Autodesk Fusion 360 part; units mm, degrees
(part 3 of 5)
sketch "gear (2)" plane through (0, 39.4, 0) normal (0, 1, 0) x (1, 0, 0) in component "Gripper gear L (printed)"
  line L0 (-136.5803, 1.2704) -> (-136.628, 0.595)
  line L1 (-136.628, 0.595) -> (-136.6893, 0.3367)
  line L2 (-136.6893, 0.3367) -> (-136.7881, 0.0815)
  line L3 (-136.7881, 0.0815) -> (-136.913, -0.1705)
  line L4 (-136.913, -0.1705) -> (-137.0604, -0.4192)
  line L5 (-137.0604, -0.4192) -> (-137.2282, -0.6639)
  line L6 (-137.2282, -0.6639) -> (-137.4152, -0.9042)
  line L7 (-137.4152, -0.9042) -> (-138.0397, -0.8)
  line L8 (-138.0397, -0.8) -> (-138.1385, -0.512)
  line L9 (-138.1385, -0.512) -> (-138.2178, -0.226)
  line L10 (-138.2178, -0.226) -> (-138.2765, 0.057)
  line L11 (-138.2765, 0.057) -> (-138.3128, 0.336)
  line L12 (-138.3128, 0.336) -> (-138.3234, 0.6093)
  line L13 (-138.3234, 0.6093) -> (-138.2975, 0.8736)
  line L14 (-138.2975, 0.8736) -> (-138.1233, 1.5279)
  line L15 (-138.1233, 1.5279) -> (-138.4949, 1.6363)
  line L16 (-138.4949, 1.6363) -> (-138.8611, 1.762)
  line L17 (-138.8611, 1.762) -> (-139.221, 1.9048)
  line L18 (-139.221, 1.9048) -> (-139.4854, 1.2814)
  line L19 (-139.4854, 1.2814) -> (-139.6273, 1.057)
  line L20 (-139.6273, 1.057) -> (-139.8036, 0.8477)
  line L21 (-139.8036, 0.8477) -> (-140.0036, 0.6499)
  line L22 (-140.0036, 0.6499) -> (-140.2237, 0.4626)
  line L23 (-140.2237, 0.4626) -> (-140.4619, 0.2856)
  line L24 (-140.4619, 0.2856) -> (-140.7167, 0.119)
  line L25 (-140.7167, 0.119) -> (-141.2736, 0.4204)
  line L26 (-141.2736, 0.4204) -> (-141.2736, 0.7249)
  line L27 (-141.2736, 0.7249) -> (-141.2557, 1.0211)
  line L28 (-141.2557, 1.0211) -> (-141.2193, 1.3078)
  line L29 (-141.2193, 1.3078) -> (-141.163, 1.5835)
  line L30 (-141.163, 1.5835) -> (-141.0843, 1.8454)
  line L31 (-141.0843, 1.8454) -> (-140.974, 2.087)
  line L32 (-140.974, 2.087) -> (-140.5967, 2.6493)
  line L33 (-140.5967, 2.6493) -> (-140.9131, 2.8725)
  line L34 (-140.9131, 2.8725) -> (-141.2186, 3.1103)
  line L35 (-141.2186, 3.1103) -> (-141.5127, 3.3622)
  line L36 (-141.5127, 3.3622) -> (-141.9651, 2.8584)
  line L37 (-141.9651, 2.8584) -> (-142.1722, 2.6922)
  line L38 (-142.1722, 2.6922) -> (-142.4069, 2.5515)
  line L39 (-142.4069, 2.5515) -> (-142.6603, 2.4294)
  line L40 (-142.6603, 2.4294) -> (-142.9293, 2.3237)
  line L41 (-142.9293, 2.3237) -> (-143.212, 2.2336)
  line L42 (-143.212, 2.2336) -> (-143.5072, 2.1588)
  line L43 (-143.5072, 2.1588) -> (-143.936, 2.6247)
  line L44 (-143.936, 2.6247) -> (-143.8371, 2.9126)
  line L45 (-143.8371, 2.9126) -> (-143.724, 3.187)
  line L46 (-143.724, 3.187) -> (-143.5965, 3.4464)
  line L47 (-143.5965, 3.4464) -> (-143.4538, 3.6888)
  line L48 (-143.4538, 3.6888) -> (-143.2942, 3.9111)
  line L49 (-143.2942, 3.9111) -> (-143.1115, 4.1037)
  line L50 (-143.1115, 4.1037) -> (-142.5721, 4.513)
  line L51 (-142.5721, 4.513) -> (-142.7988, 4.8269)
  line L52 (-142.7988, 4.8269) -> (-143.0106, 5.151)
  line L53 (-143.0106, 5.151) -> (-143.2069, 5.4847)
  line L54 (-143.2069, 5.4847) -> (-143.7984, 5.1551)
  line L55 (-143.7984, 5.1551) -> (-144.0483, 5.0652)
  line L56 (-144.0483, 5.0652) -> (-144.3159, 5.0083)
  line L57 (-144.3159, 5.0083) -> (-144.5952, 4.9751)
  line L58 (-144.5952, 4.9751) -> (-144.884, 4.9624)
  line L59 (-144.884, 4.9624) -> (-145.1807, 4.9691)
  line L60 (-145.1807, 4.9691) -> (-145.4841, 4.9942)
  line L61 (-145.4841, 4.9942) -> (-145.7384, 5.5741)
  line L62 (-145.7384, 5.5741) -> (-145.5514, 5.8143)
  line L63 (-145.5514, 5.8143) -> (-145.3553, 6.037)
  line L64 (-145.3553, 6.037) -> (-145.1505, 6.241)
  line L65 (-145.1505, 6.241) -> (-144.9368, 6.4239)
  line L66 (-144.9368, 6.4239) -> (-144.7137, 6.5823)
  line L67 (-144.7137, 6.5823) -> (-144.4783, 6.7052)
  line L68 (-144.4783, 6.7052) -> (-143.8353, 6.9172)
  line L69 (-143.8353, 6.9172) -> (-143.9478, 7.2876)
  line L70 (-143.9478, 7.2876) -> (-144.0429, 7.663)
  line L71 (-144.0429, 7.663) -> (-144.1202, 8.0423)
  line L72 (-144.1202, 8.0423) -> (-144.7866, 7.9227)
  line L73 (-144.7866, 7.9227) -> (-145.0522, 7.9188)
  line L74 (-145.0522, 7.9188) -> (-145.3237, 7.9519)
  line L75 (-145.3237, 7.9519) -> (-145.5988, 8.0111)
  line L76 (-145.5988, 8.0111) -> (-145.876, 8.0929)
  line L77 (-145.876, 8.0929) -> (-146.1544, 8.1955)
  line L78 (-146.1544, 8.1955) -> (-146.4332, 8.3178)
  line L79 (-146.4332, 8.3178) -> (-146.4855, 8.9488)
  line L80 (-146.4855, 8.9488) -> (-146.2306, 9.1153)
  line L81 (-146.2306, 9.1153) -> (-145.9729, 9.2624)
  line L82 (-145.9729, 9.2624) -> (-145.7129, 9.3887)
  line L83 (-145.7129, 9.3887) -> (-145.4514, 9.4924)
  line L84 (-145.4514, 9.4924) -> (-145.189, 9.5697)
  line L85 (-145.189, 9.5697) -> (-144.9264, 9.6096)
  line L86 (-144.9264, 9.6096) -> (-144.2494, 9.6012)
  line L87 (-144.2494, 9.6012) -> (-144.2355, 9.9882)
  line L88 (-144.2355, 9.9882) -> (-144.2036, 10.374)
  line L89 (-144.2036, 10.374) -> (-144.1535, 10.7579)
  line L90 (-144.1535, 10.7579) -> (-144.8227, 10.8612)
  line L91 (-144.8227, 10.8612) -> (-145.0751, 10.9437)
  line L92 (-145.0751, 10.9437) -> (-145.3212, 11.0632)
  line L93 (-145.3212, 11.0632) -> (-145.5621, 11.2085)
  line L94 (-145.5621, 11.2085) -> (-145.7977, 11.3759)
  line L95 (-145.7977, 11.3759) -> (-146.0278, 11.5634)
  line L96 (-146.0278, 11.5634) -> (-146.2518, 11.7695)
  line L97 (-146.2518, 11.7695) -> (-146.0964, 12.3833)
  line L98 (-146.0964, 12.3833) -> (-145.8012, 12.458)
  line L99 (-145.8012, 12.458) -> (-145.5097, 12.5134)
  line L100 (-145.5097, 12.5134) -> (-145.2228, 12.5485)
  line L101 (-145.2228, 12.5485) -> (-144.9418, 12.5617)
  line L102 (-144.9418, 12.5617) -> (-144.6684, 12.5496)
  line L103 (-144.6684, 12.5496) -> (-144.4072, 12.502)
  line L104 (-144.4072, 12.502) -> (-143.7695, 12.2743)
  line L105 (-143.7695, 12.2743) -> (-143.6308, 12.6358)
  line L106 (-143.6308, 12.6358) -> (-143.4753, 12.9904)
  line L107 (-143.4753, 12.9904) -> (-143.3033, 13.3372)
  line L108 (-143.3033, 13.3372) -> (-143.9027, 13.6521)
  line L109 (-143.9027, 13.6521) -> (-144.1147, 13.8121)
  line L110 (-144.1147, 13.8121) -> (-144.3086, 14.0051)
  line L111 (-144.3086, 14.0051) -> (-144.4893, 14.2207)
  line L112 (-144.4893, 14.2207) -> (-144.6578, 14.4556)
  line L113 (-144.6578, 14.4556) -> (-144.8145, 14.7076)
  line L114 (-144.8145, 14.7076) -> (-144.9594, 14.9753)
  line L115 (-144.9594, 14.9753) -> (-144.6131, 15.5054)
  line L116 (-144.6131, 15.5054) -> (-144.3097, 15.4802)
  line L117 (-144.3097, 15.4802) -> (-144.016, 15.4379)
  line L118 (-144.016, 15.4379) -> (-143.7332, 15.378)
  line L119 (-143.7332, 15.378) -> (-143.4631, 15.2992)
  line L120 (-143.4631, 15.2992) -> (-143.2086, 15.199)
  line L121 (-143.2086, 15.199) -> (-142.9769, 15.0692)
  line L122 (-142.9769, 15.0692) -> (-142.4477, 14.6468)
  line L123 (-142.4477, 14.6468) -> (-142.1992, 14.9436)
  line L124 (-142.1992, 14.9436) -> (-141.9369, 15.2285)
  line L125 (-141.9369, 15.2285) -> (-141.6616, 15.5007)
  line L126 (-141.6616, 15.5007) -> (-142.1263, 15.9932)
  line L127 (-142.1263, 15.9932) -> (-142.2748, 16.2133)
  line L128 (-142.2748, 16.2133) -> (-142.3956, 16.4588)
  line L129 (-142.3956, 16.4588) -> (-142.4965, 16.7214)
  line L130 (-142.4965, 16.7214) -> (-142.5796, 16.9982)
  line L131 (-142.5796, 16.9982) -> (-142.646, 17.2875)
  line L132 (-142.646, 17.2875) -> (-142.6961, 17.5877)
  line L133 (-142.6961, 17.5877) -> (-142.1965, 17.9767)
  line L134 (-142.1965, 17.9767) -> (-141.9177, 17.8543)
  line L135 (-141.9177, 17.8543) -> (-141.6536, 17.719)
  line L136 (-141.6536, 17.719) -> (-141.4056, 17.5704)
  line L137 (-141.4056, 17.5704) -> (-141.1758, 17.4082)
  line L138 (-141.1758, 17.4082) -> (-140.9675, 17.2308)
  line L139 (-140.9675, 17.2308) -> (-140.7906, 17.0328)
  line L140 (-140.7906, 17.0328) -> (-140.4272, 16.4615)
  line L141 (-140.4272, 16.4615) -> (-140.0957, 16.6615)
  line L142 (-140.0957, 16.6615) -> (-139.7552, 16.8458)
  line L143 (-139.7552, 16.8458) -> (-139.4065, 17.0139)
  line L144 (-139.4065, 17.0139) -> (-139.686, 17.6306)
  line L145 (-139.686, 17.6306) -> (-139.755, 17.887)
  line L146 (-139.755, 17.887) -> (-139.7896, 18.1584)
  line L147 (-139.7896, 18.1584) -> (-139.7997, 18.4395)
  line L148 (-139.7997, 18.4395) -> (-139.7884, 18.7283)
  line L149 (-139.7884, 18.7283) -> (-139.7573, 19.0235)
  line L150 (-139.7573, 19.0235) -> (-139.7072, 19.3238)
  line L151 (-139.7072, 19.3238) -> (-139.1083, 19.5294)
  line L152 (-139.1083, 19.5294) -> (-138.8844, 19.3231)
  line L153 (-138.8844, 19.3231) -> (-138.6786, 19.1094)
  line L154 (-138.6786, 19.1094) -> (-138.4923, 18.8884)
  line L155 (-138.4923, 18.8884) -> (-138.3276, 18.6603)
  line L156 (-138.3276, 18.6603) -> (-138.1881, 18.4249)
  line L157 (-138.1881, 18.4249) -> (-138.0851, 18.1802)
  line L158 (-138.0851, 18.1802) -> (-137.927, 17.5218)
  line L159 (-137.927, 17.5218) -> (-137.5485, 17.6034)
  line L160 (-137.5485, 17.6034) -> (-137.1666, 17.6671)
  line L161 (-137.1666, 17.6671) -> (-136.7821, 17.7128)
  line L162 (-136.7821, 17.7128) -> (-136.8463, 18.3869)
  line L163 (-136.8463, 18.3869) -> (-136.8283, 18.6518)
  line L164 (-136.8283, 18.6518) -> (-136.7729, 18.9197)
  line L165 (-136.7729, 18.9197) -> (-136.6912, 19.1889)
  line L166 (-136.6912, 19.1889) -> (-136.5867, 19.4584)
  line L167 (-136.5867, 19.4584) -> (-136.4615, 19.7274)
  line L168 (-136.4615, 19.7274) -> (-136.3166, 19.9952)
  line L169 (-136.3166, 19.9952) -> (-135.6834, 19.9952)
  line L170 (-135.6834, 19.9952) -> (-135.5385, 19.7274)
  line L171 (-135.5385, 19.7274) -> (-135.4133, 19.4584)
  line L172 (-135.4133, 19.4584) -> (-135.3088, 19.1889)
  line L173 (-135.3088, 19.1889) -> (-135.2271, 18.9197)
  line L174 (-135.2271, 18.9197) -> (-135.1717, 18.6518)
  line L175 (-135.1717, 18.6518) -> (-135.1537, 18.3869)
  line L176 (-135.1537, 18.3869) -> (-135.2179, 17.7128)
  line L177 (-135.2179, 17.7128) -> (-134.8334, 17.6671)
  line L178 (-134.8334, 17.6671) -> (-134.4515, 17.6034)
  line L179 (-134.4515, 17.6034) -> (-134.073, 17.5218)
  line L180 (-134.073, 17.5218) -> (-133.9149, 18.1802)
  line L181 (-133.9149, 18.1802) -> (-133.8119, 18.4249)
  line L182 (-133.8119, 18.4249) -> (-133.6724, 18.6603)
  line L183 (-133.6724, 18.6603) -> (-133.5077, 18.8884)
  line L184 (-133.5077, 18.8884) -> (-133.3214, 19.1094)
  line L185 (-133.3214, 19.1094) -> (-133.1156, 19.3231)
  line L186 (-133.1156, 19.3231) -> (-132.8917, 19.5294)
  line L187 (-132.8917, 19.5294) -> (-132.2928, 19.3238)
  line L188 (-132.2928, 19.3238) -> (-132.2427, 19.0235)
  line L189 (-132.2427, 19.0235) -> (-132.2116, 18.7283)
  line L190 (-132.2116, 18.7283) -> (-132.2003, 18.4395)
  line L191 (-132.2003, 18.4395) -> (-132.2104, 18.1584)
  line L192 (-132.2104, 18.1584) -> (-132.245, 17.887)
  line L193 (-132.245, 17.887) -> (-132.314, 17.6306)
  line L194 (-132.314, 17.6306) -> (-132.5935, 17.0139)
  line L195 (-132.5935, 17.0139) -> (-132.2448, 16.8458)
  line L196 (-132.2448, 16.8458) -> (-131.9043, 16.6615)
  line L197 (-131.9043, 16.6615) -> (-131.5728, 16.4615)
  line L198 (-131.5728, 16.4615) -> (-131.2094, 17.0328)
  line L199 (-131.2094, 17.0328) -> (-131.0325, 17.2308)
  line L200 (-131.0325, 17.2308) -> (-130.8242, 17.4082)
  line L201 (-130.8242, 17.4082) -> (-130.5944, 17.5704)
  line L202 (-130.5944, 17.5704) -> (-130.3464, 17.719)
  line L203 (-130.3464, 17.719) -> (-130.0823, 17.8543)
  line L204 (-130.0823, 17.8543) -> (-129.8035, 17.9767)
  line L205 (-129.8035, 17.9767) -> (-129.3039, 17.5877)
  line L206 (-129.3039, 17.5877) -> (-129.354, 17.2875)
  line L207 (-129.354, 17.2875) -> (-129.4204, 16.9982)
  line L208 (-129.4204, 16.9982) -> (-129.5035, 16.7214)
  line L209 (-129.5035, 16.7214) -> (-129.6044, 16.4588)
  line L210 (-129.6044, 16.4588) -> (-129.7252, 16.2133)
  line L211 (-129.7252, 16.2133) -> (-129.8737, 15.9932)
  line L212 (-129.8737, 15.9932) -> (-130.3384, 15.5007)
  line L213 (-130.3384, 15.5007) -> (-130.0631, 15.2285)
  line L214 (-130.0631, 15.2285) -> (-129.8008, 14.9436)
  line L215 (-129.8008, 14.9436) -> (-129.5523, 14.6468)
  line L216 (-129.5523, 14.6468) -> (-129.0231, 15.0692)
  line L217 (-129.0231, 15.0692) -> (-128.7914, 15.199)
  line L218 (-128.7914, 15.199) -> (-128.5369, 15.2992)
  line L219 (-128.5369, 15.2992) -> (-128.2668, 15.378)
  line L220 (-128.2668, 15.378) -> (-127.984, 15.4379)
  line L221 (-127.984, 15.4379) -> (-127.6903, 15.4802)
  line L222 (-127.6903, 15.4802) -> (-127.3869, 15.5054)
  line L223 (-127.3869, 15.5054) -> (-127.0406, 14.9753)
  line L224 (-127.0406, 14.9753) -> (-127.1855, 14.7076)
  line L225 (-127.1855, 14.7076) -> (-127.3422, 14.4556)
  line L226 (-127.3422, 14.4556) -> (-127.5107, 14.2207)
  line L227 (-127.5107, 14.2207) -> (-127.6914, 14.0051)
  line L228 (-127.6914, 14.0051) -> (-127.8853, 13.8121)
  line L229 (-127.8853, 13.8121) -> (-128.0973, 13.6521)
  line L230 (-128.0973, 13.6521) -> (-128.6967, 13.3372)
  line L231 (-128.6967, 13.3372) -> (-128.5247, 12.9904)
  line L232 (-128.5247, 12.9904) -> (-128.3692, 12.6358)
  line L233 (-128.3692, 12.6358) -> (-128.2305, 12.2743)
  line L234 (-128.2305, 12.2743) -> (-127.5928, 12.502)
  line L235 (-127.5928, 12.502) -> (-127.3316, 12.5496)
  line L236 (-127.3316, 12.5496) -> (-127.0582, 12.5617)
  line L237 (-127.0582, 12.5617) -> (-126.7772, 12.5485)
  line L238 (-126.7772, 12.5485) -> (-126.4903, 12.5134)
  line L239 (-126.4903, 12.5134) -> (-126.1988, 12.458)
  line L240 (-126.1988, 12.458) -> (-125.9036, 12.3833)
  line L241 (-125.9036, 12.3833) -> (-125.7482, 11.7695)
  line L242 (-125.7482, 11.7695) -> (-125.9722, 11.5634)
  line L243 (-125.9722, 11.5634) -> (-126.2023, 11.3759)
  line L244 (-126.2023, 11.3759) -> (-126.4379, 11.2085)
  line L245 (-126.4379, 11.2085) -> (-126.6788, 11.0632)
  line L246 (-126.6788, 11.0632) -> (-126.9249, 10.9437)
  line L247 (-126.9249, 10.9437) -> (-127.1773, 10.8612)
  line L248 (-127.1773, 10.8612) -> (-127.8465, 10.7579)
  line L249 (-127.8465, 10.7579) -> (-127.7964, 10.374)
  line L250 (-127.7964, 10.374) -> (-127.7645, 9.9882)
  line L251 (-127.7645, 9.9882) -> (-127.7506, 9.6012)
  line L252 (-127.7506, 9.6012) -> (-127.0736, 9.6096)
  line L253 (-127.0736, 9.6096) -> (-126.811, 9.5697)
  line L254 (-126.811, 9.5697) -> (-126.5486, 9.4924)
  line L255 (-126.5486, 9.4924) -> (-126.2871, 9.3887)
  line L256 (-126.2871, 9.3887) -> (-126.0271, 9.2624)
  line L257 (-126.0271, 9.2624) -> (-125.7694, 9.1153)
  line L258 (-125.7694, 9.1153) -> (-125.5145, 8.9488)
  line L259 (-125.5145, 8.9488) -> (-125.5668, 8.3178)
  line L260 (-125.5668, 8.3178) -> (-125.8456, 8.1955)
  line L261 (-125.8456, 8.1955) -> (-126.124, 8.0929)
  line L262 (-126.124, 8.0929) -> (-126.4012, 8.0111)
  line L263 (-126.4012, 8.0111) -> (-126.6763, 7.9519)
  line L264 (-126.6763, 7.9519) -> (-126.9478, 7.9188)
  line L265 (-126.9478, 7.9188) -> (-127.2134, 7.9227)
  line L266 (-127.2134, 7.9227) -> (-127.8798, 8.0423)
  line L267 (-127.8798, 8.0423) -> (-127.9571, 7.663)
  line L268 (-127.9571, 7.663) -> (-128.0522, 7.2876)
  line L269 (-128.0522, 7.2876) -> (-128.1647, 6.9172)
  line L270 (-128.1647, 6.9172) -> (-127.5217, 6.7052)
  line L271 (-127.5217, 6.7052) -> (-127.2863, 6.5823)
  line L272 (-127.2863, 6.5823) -> (-127.0632, 6.4239)
  line L273 (-127.0632, 6.4239) -> (-126.8495, 6.241)
  line L274 (-126.8495, 6.241) -> (-126.6447, 6.037)
  line L275 (-126.6447, 6.037) -> (-126.4486, 5.8143)
  line L276 (-126.4486, 5.8143) -> (-126.2616, 5.5741)
  line L277 (-126.2616, 5.5741) -> (-126.5159, 4.9942)
  line L278 (-126.5159, 4.9942) -> (-126.8193, 4.9691)
  line L279 (-126.8193, 4.9691) -> (-127.116, 4.9624)
  line L280 (-127.116, 4.9624) -> (-127.4048, 4.9751)
  line L281 (-127.4048, 4.9751) -> (-127.6841, 5.0083)
  line L282 (-127.6841, 5.0083) -> (-127.9517, 5.0652)
  line L283 (-127.9517, 5.0652) -> (-128.2016, 5.1551)
  line L284 (-128.2016, 5.1551) -> (-128.7931, 5.4847)
  line L285 (-128.7931, 5.4847) -> (-128.9894, 5.151)
  line L286 (-128.9894, 5.151) -> (-129.2012, 4.8269)
  line L287 (-129.2012, 4.8269) -> (-129.4279, 4.513)
  line L288 (-129.4279, 4.513) -> (-128.8885, 4.1037)
  line L289 (-128.8885, 4.1037) -> (-128.7058, 3.9111)
  line L290 (-128.7058, 3.9111) -> (-128.5462, 3.6888)
  line L291 (-128.5462, 3.6888) -> (-128.4035, 3.4464)
  line L292 (-128.4035, 3.4464) -> (-128.276, 3.187)
  line L293 (-128.276, 3.187) -> (-128.1629, 2.9126)
  line L294 (-128.1629, 2.9126) -> (-128.064, 2.6247)
  line L295 (-128.064, 2.6247) -> (-128.4928, 2.1588)
  line L296 (-128.4928, 2.1588) -> (-128.788, 2.2336)
  line L297 (-128.788, 2.2336) -> (-129.0707, 2.3237)
  line L298 (-129.0707, 2.3237) -> (-129.3397, 2.4294)
  line L299 (-129.3397, 2.4294) -> (-129.5931, 2.5515)
  line L300 (-129.5931, 2.5515) -> (-129.8278, 2.6922)
  line L301 (-129.8278, 2.6922) -> (-130.0349, 2.8584)
  line L302 (-130.0349, 2.8584) -> (-130.4873, 3.3622)
  line L303 (-130.4873, 3.3622) -> (-130.7814, 3.1103)
  line L304 (-130.7814, 3.1103) -> (-131.0869, 2.8725)
  line L305 (-131.0869, 2.8725) -> (-131.4033, 2.6493)
  line L306 (-131.4033, 2.6493) -> (-131.026, 2.087)
  line L307 (-131.026, 2.087) -> (-130.9157, 1.8454)
  line L308 (-130.9157, 1.8454) -> (-130.837, 1.5835)
  line L309 (-130.837, 1.5835) -> (-130.7807, 1.3078)
  line L310 (-130.7807, 1.3078) -> (-130.7443, 1.0211)
  line L311 (-130.7443, 1.0211) -> (-130.7264, 0.7249)
  line L312 (-130.7264, 0.7249) -> (-130.7264, 0.4204)
  line L313 (-130.7264, 0.4204) -> (-131.2833, 0.119)
  line L314 (-131.2833, 0.119) -> (-131.5381, 0.2856)
  line L315 (-131.5381, 0.2856) -> (-131.7763, 0.4626)
  line L316 (-131.7763, 0.4626) -> (-131.9964, 0.6499)
  line L317 (-131.9964, 0.6499) -> (-132.1964, 0.8477)
  line L318 (-132.1964, 0.8477) -> (-132.3727, 1.057)
  line L319 (-132.3727, 1.057) -> (-132.5146, 1.2814)
  line L320 (-132.5146, 1.2814) -> (-132.779, 1.9048)
  line L321 (-132.779, 1.9048) -> (-133.1389, 1.762)
  line L322 (-133.1389, 1.762) -> (-133.5051, 1.6363)
  line L323 (-133.5051, 1.6363) -> (-133.8767, 1.5279)
  line L324 (-133.8767, 1.5279) -> (-133.7025, 0.8736)
  line L325 (-133.7025, 0.8736) -> (-133.6766, 0.6093)
  line L326 (-133.6766, 0.6093) -> (-133.6872, 0.336)
  line L327 (-133.6872, 0.336) -> (-133.7235, 0.057)
  line L328 (-133.7235, 0.057) -> (-133.7822, -0.226)
  line L329 (-133.7822, -0.226) -> (-133.8615, -0.512)
  line L330 (-133.8615, -0.512) -> (-133.9603, -0.8)
  line L331 (-133.9603, -0.8) -> (-134.5848, -0.9042)
  line L332 (-134.5848, -0.9042) -> (-134.7718, -0.6639)
  line L333 (-134.7718, -0.6639) -> (-134.9396, -0.4192)
  line L334 (-134.9396, -0.4192) -> (-135.087, -0.1705)
  line L335 (-135.087, -0.1705) -> (-135.2119, 0.0815)
  line L336 (-135.2119, 0.0815) -> (-135.3107, 0.3367)
  line L337 (-135.3107, 0.3367) -> (-135.372, 0.595)
  line L338 (-135.372, 0.595) -> (-135.4197, 1.2704)
  line L339 (-135.4197, 1.2704) -> (-135.8064, 1.2523)
  line L340 (-135.8064, 1.2523) -> (-136.1936, 1.2523)
  line L341 (-136.1936, 1.2523) -> (-136.5803, 1.2704)
extrude "gear (1)'" add sketch "gear (2)" along normal blind 6 separate body makes body 23 in component "Gripper gear L (printed)"
sketch "finger tongue (2)" plane through (0, 39.4, 0) normal (0, 1, 0) x (1, 0, 0) in component "Gripper gear L (printed)"
  line L0 (-131, 13.5) -> (-108, 13.5)
  line L1 (-108, 13.5) -> (-108, 5.5)
  line L2 (-108, 5.5) -> (-131, 5.5)
  line L3 (-131, 5.5) -> (-131, 13.5)
extrude "finger tongue (1)'" add sketch "finger tongue (2)" along normal blind 6 separate body makes body 24 in component "Gripper gear L (printed)"
combine "Combine1'''" operation add target body 23 tool bodies 24 in component "Gripper gear L (printed)"
ref_plane "WorkPlane2" through (0, 38.4, 0) normal (0, 1, 0) x (0, 0, 1) in component "Gripper gear L (printed)"
sketch "axle bore (2)" plane through (0, 38.4, 0) normal (0, 1, 0) x (1, 0, 0) in component "Gripper gear L (printed)"
  circle A0 centre (-136, 9.5) radius 1.7
extrude "axle bore (1)'" cut sketch "axle bore (2)" along normal blind 8 bodies 23 in component "Gripper gear L (printed)"
sketch "finger insert hole (2)" plane through (0, 38.4, 0) normal (0, 1, 0) x (1, 0, 0) in component "Gripper gear L (printed)"
  circle A0 centre (-114, 9.5) radius 2
extrude "finger insert hole (1)'" cut sketch "finger insert hole (2)" along normal blind 8 bodies 23 in component "Gripper gear L (printed)"
ref_plane "WorkPlane1" through (0, 0, -4) normal (0, 0, 1) x (1, 0, 0) in component "Gripper trigger (printed)"
sketch "lever" plane through (0, 0, -4) normal (0, 0, 1) x (1, 0, 0) in component "Gripper trigger (printed)"
  line L0 (103.845, -2.8975) -> (106.6597, -9.2424)
  line L1 (106.6597, -9.2424) -> (109.3343, -15.6275)
  line L2 (109.3343, -15.6275) -> (111.7503, -22.0868)
  line L3 (111.7503, -22.0868) -> (113.8282, -28.6431)
  line L4 (113.8282, -28.6431) -> (115.5403, -35.3042)
  line L5 (115.5403, -35.3042) -> (116.9144, -42.0622)
  line L6 (116.9144, -42.0622) -> (118.0297, -48.8945)
  line L7 (118.0297, -48.8945) -> (119.0051, -55.7668)
  line L8 (119.0051, -55.7668) -> (111.315, -57.9719)
  line L9 (111.315, -57.9719) -> (96.155, -5.1025)
  line L10 (96.155, -5.1025) -> (103.845, -2.8975)
extrude "lever (1)" add sketch "lever" along normal blind 20 separate body makes body 25 in component "Gripper trigger (printed)"
ref_plane "WorkPlane2" through (0, 0, -3.99) normal (0, 0, 1) x (1, 0, 0) in component "Gripper trigger (printed)"
sketch "eye" plane through (0, 0, -3.99) normal (0, 0, 1) x (1, 0, 0) in component "Gripper trigger (printed)"
  circle A0 centre (100, -4) radius 5
extrude "eye (1)" add sketch "eye" along normal blind 23.98 separate body makes body 26 in component "Gripper trigger (printed)"
ref_plane "WorkPlane3" through (0, 0, 12) normal (0, 0, 1) x (1, 0, 0) in component "Gripper trigger (printed)"
sketch "cable horn" plane through (0, 0, 12) normal (0, 0, 1) x (1, 0, 0) in component "Gripper trigger (printed)"
  line L0 (95, -4) -> (105, -4)
  line L1 (105, -4) -> (105, 17)
  line L2 (105, 17) -> (95, 17)
  line L3 (95, 17) -> (95, -4)
extrude "cable horn (1)" add sketch "cable horn" along normal blind 8 separate body makes body 27 in component "Gripper trigger (printed)"
combine "Combine1''''" operation add target body 25 tool bodies 26 in component "Gripper trigger (printed)"
combine "Combine2'''" operation add target body 25 tool bodies 27 in component "Gripper trigger (printed)"
ref_plane "WorkPlane4" through (0, 0, -5) normal (0, 0, 1) x (1, 0, 0) in component "Gripper trigger (printed)"
sketch "pivot bore" plane through (0, 0, -5) normal (0, 0, 1) x (1, 0, 0) in component "Gripper trigger (printed)"
  circle A0 centre (100, -4) radius 1.7
extrude "pivot bore (1)" cut sketch "pivot bore" along normal blind 27 bodies 25 in component "Gripper trigger (printed)"
ref_plane "WorkPlane5" through (0, 0, 15.1) normal (0, 0, 1) x (1, 0, 0) in component "Gripper trigger (printed)"
sketch "wire slot" plane through (0, 0, 15.1) normal (0, 0, 1) x (1, 0, 0) in component "Gripper trigger (printed)"
  line L0 (94, 12.6) -> (106, 12.6)
  line L1 (106, 12.6) -> (106, 18)
  line L2 (106, 18) -> (94, 18)
  line L3 (94, 18) -> (94, 12.6)
extrude "wire slot (1)" cut sketch "wire slot" along normal blind 1.8 bodies 25 in component "Gripper trigger (printed)"
ref_plane "WorkPlane1" through (0, 24.2, 0) normal (0, 1, 0) x (0, 0, 1) in component "Gripper pusher (printed)"
sketch "lever (2)" plane through (0, 24.2, 0) normal (0, 1, 0) x (1, 0, 0) in component "Gripper pusher (printed)"
  line L0 (125.993, -57.7785) -> (124.693, -37.2785)
  line L1 (124.693, -37.2785) -> (117.707, -37.7215)
  line L2 (117.707, -37.7215) -> (119.007, -58.2215)
  line L3 (119.007, -58.2215) -> (125.993, -57.7785)
extrude "lever (1)'" add sketch "lever (2)" along normal blind 4.8 separate body makes body 28 in component "Gripper pusher (printed)"
sketch "hub" plane through (0, 24.2, 0) normal (0, 1, 0) x (1, 0, 0) in component "Gripper pusher (printed)"
  circle A0 centre (122.5, -58) radius 5
extrude "hub (1)" add sketch "hub" along normal blind 4.8 separate body makes body 29 in component "Gripper pusher (printed)"
combine "Combine1'''''" operation add target body 28 tool bodies 29 in component "Gripper pusher (printed)"
ref_plane "WorkPlane2" through (0, 23.2, 0) normal (0, 1, 0) x (0, 0, 1) in component "Gripper pusher (printed)"
sketch "pivot hole" plane through (0, 23.2, 0) normal (0, 1, 0) x (1, 0, 0) in component "Gripper pusher (printed)"
  circle A0 centre (122.5, -58) radius 1.7
extrude "pivot hole (1)" cut sketch "pivot hole" along normal blind 7 bodies 28 in component "Gripper pusher (printed)"
ref_plane "WorkPlane3" through (116.1203, 0, 0) normal (1, 0, 0) x (0, 1, 0) in component "Gripper pusher (printed)"
sketch "cable hole" plane through (116.1203, 0, 0) normal (1, 0, 0) x (0, 0, -1) in component "Gripper pusher (printed)"
  circle A0 centre (-52.012, 26.6) radius 0.9
extrude "cable hole (1)" cut sketch "cable hole" along normal blind 12 bodies 28 in component "Gripper pusher (printed)"
ref_plane "WorkPlane1" through (0, 0, -12) normal (0, 0, 1) x (1, 0, 0) in component "Gripper handle (printed)"
sketch "arm" plane through (0, 0, -12) normal (0, 0, 1) x (1, 0, 0) in component "Gripper handle (printed)"
  line L0 (8.3, 6) -> (140, 6)
  line L1 (140, 6) -> (140, 20)
  line L2 (140, 20) -> (8.3, 20)
  line L3 (8.3, 20) -> (8.3, 6)
extrude "arm (1)" add sketch "arm" along normal blind 36 separate body makes body 30 in component "Gripper handle (printed)"
ref_plane "WorkPlane2" through (0, 0, 23.99) normal (0, 0, 1) x (1, 0, 0) in component "Gripper handle (printed)"
sketch "pusher bracket" plane through (0, 0, 23.99) normal (0, 0, 1) x (1, 0, 0) in component "Gripper handle (printed)"
  line L0 (118, 6) -> (131, 6)
  line L1 (131, 6) -> (131, 24)
  line L2 (131, 24) -> (118, 24)
  line L3 (118, 24) -> (118, 6)
extrude "pusher bracket (1)" add sketch "pusher bracket" along normal blind 40.01 separate body makes body 31 in component "Gripper handle (printed)"
ref_plane "WorkPlane3" through (0, -105, 0) normal (0, 1, 0) x (0, 0, 1) in component "Gripper handle (printed)"
sketch "grip" plane through (0, -105, 0) normal (0, 1, 0) x (1, 0, 0) in component "Gripper handle (printed)"
  line L0 (81, -6) -> (80.4548, -10.4724)
  line L1 (80.4548, -10.4724) -> (78.8564, -14.64)
  line L2 (78.8564, -14.64) -> (76.3137, -18.2188)
  line L3 (76.3137, -18.2188) -> (73, -20.9649)
  line L4 (73, -20.9649) -> (69.1411, -22.6912)
  line L5 (69.1411, -22.6912) -> (65, -23.28)
  line L6 (65, -23.28) -> (60.8589, -22.6912)
  line L7 (60.8589, -22.6912) -> (57, -20.9649)
  line L8 (57, -20.9649) -> (53.6863, -18.2188)
  line L9 (53.6863, -18.2188) -> (51.1436, -14.64)
  line L10 (51.1436, -14.64) -> (49.5452, -10.4724)
  line L11 (49.5452, -10.4724) -> (49, -6)
  line L12 (49, -6) -> (49.5452, -1.5276)
  line L13 (49.5452, -1.5276) -> (51.1436, 2.64)
  line L14 (51.1436, 2.64) -> (53.6863, 6.2188)
  line L15 (53.6863, 6.2188) -> (57, 8.9649)
  line L16 (57, 8.9649) -> (60.8589, 10.6912)
  line L17 (60.8589, 10.6912) -> (65, 11.28)
  line L18 (65, 11.28) -> (69.1411, 10.6912)
  line L19 (69.1411, 10.6912) -> (73, 8.9649)
  line L20 (73, 8.9649) -> (76.3137, 6.2188)
  line L21 (76.3137, 6.2188) -> (78.8564, 2.64)
  line L22 (78.8564, 2.64) -> (80.4548, -1.5276)
  line L23 (80.4548, -1.5276) -> (81, -6)
extrude "grip (1)" add sketch "grip" along normal blind 111.01 separate body makes body 32 in component "Gripper handle (printed)"
ref_plane "WorkPlane4" through (0, 0, -8.5) normal (0, 0, 1) x (1, 0, 0) in component "Gripper handle (printed)"
sketch "trigger cheek" plane through (0, 0, -8.5) normal (0, 0, 1) x (1, 0, 0) in component "Gripper handle (printed)"
  line L0 (81.5, -10) -> (108, -10)
  line L1 (108, -10) -> (108, 6.01)
  line L2 (108, 6.01) -> (81.5, 6.01)
  line L3 (81.5, 6.01) -> (81.5, -10)
extrude "trigger cheek (1)" add sketch "trigger cheek" along normal blind 4 separate body makes body 33 in component "Gripper handle (printed)"
ref_plane "WorkPlane5" through (0, 0, 20.5) normal (0, 0, 1) x (1, 0, 0) in component "Gripper handle (printed)"
sketch "trigger cheek (1)" plane through (0, 0, 20.5) normal (0, 0, 1) x (1, 0, 0) in component "Gripper handle (printed)"
  line L0 (81.5, -10) -> (108, -10)
  line L1 (108, -10) -> (108, 6.01)
  line L2 (108, 6.01) -> (81.5, 6.01)
  line L3 (81.5, 6.01) -> (81.5, -10)
extrude "trigger cheek (2)" add sketch "trigger cheek (1)" along normal blind 3.5 separate body makes body 34 in component "Gripper handle (printed)"
ref_plane "WorkPlane6" through (0, 16.5, 0) normal (0, 1, 0) x (0, 0, 1) in component "Gripper handle (printed)"
sketch "rack (2)" plane through (0, 16.5, 0) normal (0, 1, 0) x (1, 0, 0) in component "Gripper handle (printed)"
  line L0 (8.3, -11.5) -> (8.3, -12)
  line L1 (8.3, -12) -> (10.5517, -12)
  line L2 (10.5517, -12) -> (11.3706, -14.25)
  line L3 (11.3706, -14.25) -> (12.2134, -14.25)
  line L4 (12.2134, -14.25) -> (13.0324, -12)
  line L5 (13.0324, -12) -> (13.6933, -12)
  line L6 (13.6933, -12) -> (14.5122, -14.25)
  line L7 (14.5122, -14.25) -> (15.355, -14.25)
  line L8 (15.355, -14.25) -> (16.174, -12)
  line L9 (16.174, -12) -> (16.8348, -12)
  line L10 (16.8348, -12) -> (17.6538, -14.25)
  line L11 (17.6538, -14.25) -> (18.4966, -14.25)
  line L12 (18.4966, -14.25) -> (19.3156, -12)
  line L13 (19.3156, -12) -> (19.9764, -12)
  line L14 (19.9764, -12) -> (20.7954, -14.25)
  line L15 (20.7954, -14.25) -> (21.6382, -14.25)
  line L16 (21.6382, -14.25) -> (22.4572, -12)
  line L17 (22.4572, -12) -> (23.118, -12)
  line L18 (23.118, -12) -> (23.937, -14.25)
  line L19 (23.937, -14.25) -> (24.7798, -14.25)
  line L20 (24.7798, -14.25) -> (25.5988, -12)
  line L21 (25.5988, -12) -> (26.2596, -12)
  line L22 (26.2596, -12) -> (27.0786, -14.25)
  line L23 (27.0786, -14.25) -> (27.9214, -14.25)
  line L24 (27.9214, -14.25) -> (28.7403, -12)
  line L25 (28.7403, -12) -> (29.4012, -12)
  line L26 (29.4012, -12) -> (30.2201, -14.25)
  line L27 (30.2201, -14.25) -> (31.063, -14.25)
  line L28 (31.063, -14.25) -> (31.8819, -12)
  line L29 (31.8819, -12) -> (32.5428, -12)
  line L30 (32.5428, -12) -> (33.3617, -14.25)
  line L31 (33.3617, -14.25) -> (34.2046, -14.25)
  line L32 (34.2046, -14.25) -> (35.0235, -12)
  line L33 (35.0235, -12) -> (35.6844, -12)
  line L34 (35.6844, -12) -> (36.5033, -14.25)
  line L35 (36.5033, -14.25) -> (37.3462, -14.25)
  line L36 (37.3462, -14.25) -> (38.1651, -12)
  line L37 (38.1651, -12) -> (38.826, -12)
  line L38 (38.826, -12) -> (39.6449, -14.25)
  line L39 (39.6449, -14.25) -> (40.4878, -14.25)
  line L40 (40.4878, -14.25) -> (41.3067, -12)
  line L41 (41.3067, -12) -> (41.9676, -12)
  line L42 (41.9676, -12) -> (42.7865, -14.25)
  line L43 (42.7865, -14.25) -> (43.6294, -14.25)
  line L44 (43.6294, -14.25) -> (44.4483, -12)
  line L45 (44.4483, -12) -> (45.1092, -12)
  line L46 (45.1092, -12) -> (45.9281, -14.25)
  line L47 (45.9281, -14.25) -> (46.771, -14.25)
  line L48 (46.771, -14.25) -> (47.5899, -12)
  line L49 (47.5899, -12) -> (48.2508, -12)
  line L50 (48.2508, -12) -> (49.0697, -14.25)
  line L51 (49.0697, -14.25) -> (49.9126, -14.25)
  line L52 (49.9126, -14.25) -> (50.7315, -12)
  line L53 (50.7315, -12) -> (51.3924, -12)
  line L54 (51.3924, -12) -> (52.2113, -14.25)
  line L55 (52.2113, -14.25) -> (53.0542, -14.25)
  line L56 (53.0542, -14.25) -> (53.8731, -12)
  line L57 (53.8731, -12) -> (54.534, -12)
  line L58 (54.534, -12) -> (55.3529, -14.25)
  line L59 (55.3529, -14.25) -> (56.1957, -14.25)
  line L60 (56.1957, -14.25) -> (57.0147, -12)
  line L61 (57.0147, -12) -> (57.6756, -12)
  line L62 (57.6756, -12) -> (58.4945, -14.25)
  line L63 (58.4945, -14.25) -> (59.3373, -14.25)
  line L64 (59.3373, -14.25) -> (60.1563, -12)
  line L65 (60.1563, -12) -> (60.8171, -12)
  line L66 (60.8171, -12) -> (61.6361, -14.25)
  line L67 (61.6361, -14.25) -> (62.4789, -14.25)
  line L68 (62.4789, -14.25) -> (63.2979, -12)
  line L69 (63.2979, -12) -> (63.9587, -12)
  line L70 (63.9587, -12) -> (64.7777, -14.25)
  line L71 (64.7777, -14.25) -> (65.6205, -14.25)
  line L72 (65.6205, -14.25) -> (66.4395, -12)
  line L73 (66.4395, -12) -> (67.1003, -12)
  line L74 (67.1003, -12) -> (67.9193, -14.25)
  line L75 (67.9193, -14.25) -> (68.7621, -14.25)
  line L76 (68.7621, -14.25) -> (69.5811, -12)
  line L77 (69.5811, -12) -> (70.2419, -12)
  line L78 (70.2419, -12) -> (71.0609, -14.25)
  line L79 (71.0609, -14.25) -> (71.9037, -14.25)
  line L80 (71.9037, -14.25) -> (72.7226, -12)
  line L81 (72.7226, -12) -> (73.3835, -12)
  line L82 (73.3835, -12) -> (74.2024, -14.25)
  line L83 (74.2024, -14.25) -> (75.0453, -14.25)
  line L84 (75.0453, -14.25) -> (75.8642, -12)
  line L85 (75.8642, -12) -> (76.5251, -12)
  line L86 (76.5251, -12) -> (77.344, -14.25)
  line L87 (77.344, -14.25) -> (78.1869, -14.25)
  line L88 (78.1869, -14.25) -> (79.0058, -12)
  line L89 (79.0058, -12) -> (79.6667, -12)
  line L90 (79.6667, -12) -> (80.4856, -14.25)
  line L91 (80.4856, -14.25) -> (81.3285, -14.25)
  line L92 (81.3285, -14.25) -> (82.1474, -12)
  line L93 (82.1474, -12) -> (82.8083, -12)
  line L94 (82.8083, -12) -> (83.6272, -14.25)
  line L95 (83.6272, -14.25) -> (84.4701, -14.25)
  line L96 (84.4701, -14.25) -> (85.289, -12)
  line L97 (85.289, -12) -> (85.9499, -12)
  line L98 (85.9499, -12) -> (86.7688, -14.25)
  line L99 (86.7688, -14.25) -> (87.6117, -14.25)
  line L100 (87.6117, -14.25) -> (88.4306, -12)
  line L101 (88.4306, -12) -> (89.0915, -12)
  line L102 (89.0915, -12) -> (89.9104, -14.25)
  line L103 (89.9104, -14.25) -> (90.7533, -14.25)
  line L104 (90.7533, -14.25) -> (91.5722, -12)
  line L105 (91.5722, -12) -> (92.2331, -12)
  line L106 (92.2331, -12) -> (93.052, -14.25)
  line L107 (93.052, -14.25) -> (93.8949, -14.25)
  line L108 (93.8949, -14.25) -> (94.7138, -12)
  line L109 (94.7138, -12) -> (95.3747, -12)
  line L110 (95.3747, -12) -> (96.1936, -14.25)
  line L111 (96.1936, -14.25) -> (97.0365, -14.25)
  line L112 (97.0365, -14.25) -> (97.8554, -12)
  line L113 (97.8554, -12) -> (98.5163, -12)
  line L114 (98.5163, -12) -> (99.3352, -14.25)
  line L115 (99.3352, -14.25) -> (100.178, -14.25)
  line L116 (100.178, -14.25) -> (100.997, -12)
  line L117 (100.997, -12) -> (101.6578, -12)
  line L118 (101.6578, -12) -> (102.4768, -14.25)
  line L119 (102.4768, -14.25) -> (103.3196, -14.25)
  line L120 (103.3196, -14.25) -> (104.1386, -12)
  line L121 (104.1386, -12) -> (104.7994, -12)
  line L122 (104.7994, -12) -> (105.6184, -14.25)
  line L123 (105.6184, -14.25) -> (106.4612, -14.25)
  line L124 (106.4612, -14.25) -> (107.2802, -12)
  line L125 (107.2802, -12) -> (107.941, -12)
  line L126 (107.941, -12) -> (108.76, -14.25)
  line L127 (108.76, -14.25) -> (109.6028, -14.25)
  line L128 (109.6028, -14.25) -> (110.4218, -12)
  line L129 (110.4218, -12) -> (111.0826, -12)
  line L130 (111.0826, -12) -> (111.9016, -14.25)
  line L131 (111.9016, -14.25) -> (112.7444, -14.25)
  line L132 (112.7444, -14.25) -> (113.5633, -12)
  line L133 (113.5633, -12) -> (114.2242, -12)
  line L134 (114.2242, -12) -> (115.0432, -14.25)
  line L135 (115.0432, -14.25) -> (115.886, -14.25)
  line L136 (115.886, -14.25) -> (116.7049, -12)
  line L137 (116.7049, -12) -> (118, -12)
  line L138 (118, -12) -> (118, -11.5)
  line L139 (118, -11.5) -> (8.3, -11.5)
extrude "rack (1)'" add sketch "rack (2)" along normal blind 3.49 separate body makes body 35 in component "Gripper handle (printed)"
sketch "rack (1) (2)" plane through (0, 16.5, 0) normal (0, 1, 0) x (1, 0, 0) in component "Gripper handle (printed)"
  line L0 (8.3, 11.5) -> (8.3, 12)
  line L1 (8.3, 12) -> (10.5517, 12)
  line L2 (10.5517, 12) -> (11.3706, 14.25)
  line L3 (11.3706, 14.25) -> (12.2134, 14.25)
  line L4 (12.2134, 14.25) -> (13.0324, 12)
  line L5 (13.0324, 12) -> (13.6933, 12)
  line L6 (13.6933, 12) -> (14.5122, 14.25)
  line L7 (14.5122, 14.25) -> (15.355, 14.25)
  line L8 (15.355, 14.25) -> (16.174, 12)
  line L9 (16.174, 12) -> (16.8348, 12)
  line L10 (16.8348, 12) -> (17.6538, 14.25)
  line L11 (17.6538, 14.25) -> (18.4966, 14.25)
  line L12 (18.4966, 14.25) -> (19.3156, 12)
  line L13 (19.3156, 12) -> (19.9764, 12)
  line L14 (19.9764, 12) -> (20.7954, 14.25)
  line L15 (20.7954, 14.25) -> (21.6382, 14.25)
  line L16 (21.6382, 14.25) -> (22.4572, 12)
  line L17 (22.4572, 12) -> (23.118, 12)
  line L18 (23.118, 12) -> (23.937, 14.25)
  line L19 (23.937, 14.25) -> (24.7798, 14.25)
  line L20 (24.7798, 14.25) -> (25.5988, 12)
  line L21 (25.5988, 12) -> (26.2596, 12)
  line L22 (26.2596, 12) -> (27.0786, 14.25)
  line L23 (27.0786, 14.25) -> (27.9214, 14.25)
  line L24 (27.9214, 14.25) -> (28.7403, 12)
  line L25 (28.7403, 12) -> (29.4012, 12)
  line L26 (29.4012, 12) -> (30.2201, 14.25)
  line L27 (30.2201, 14.25) -> (31.063, 14.25)
  line L28 (31.063, 14.25) -> (31.8819, 12)
  line L29 (31.8819, 12) -> (32.5428, 12)
  line L30 (32.5428, 12) -> (33.3617, 14.25)
  line L31 (33.3617, 14.25) -> (34.2046, 14.25)
  line L32 (34.2046, 14.25) -> (35.0235, 12)
  line L33 (35.0235, 12) -> (35.6844, 12)
  line L34 (35.6844, 12) -> (36.5033, 14.25)
  line L35 (36.5033, 14.25) -> (37.3462, 14.25)
  line L36 (37.3462, 14.25) -> (38.1651, 12)
  line L37 (38.1651, 12) -> (38.826, 12)
  line L38 (38.826, 12) -> (39.6449, 14.25)
  line L39 (39.6449, 14.25) -> (40.4878, 14.25)
  line L40 (40.4878, 14.25) -> (41.3067, 12)
  line L41 (41.3067, 12) -> (41.9676, 12)
  line L42 (41.9676, 12) -> (42.7865, 14.25)
  line L43 (42.7865, 14.25) -> (43.6294, 14.25)
  line L44 (43.6294, 14.25) -> (44.4483, 12)
  line L45 (44.4483, 12) -> (45.1092, 12)
  line L46 (45.1092, 12) -> (45.9281, 14.25)
  line L47 (45.9281, 14.25) -> (46.771, 14.25)
  line L48 (46.771, 14.25) -> (47.5899, 12)
  line L49 (47.5899, 12) -> (48.2508, 12)
  line L50 (48.2508, 12) -> (49.0697, 14.25)
  line L51 (49.0697, 14.25) -> (49.9126, 14.25)
  line L52 (49.9126, 14.25) -> (50.7315, 12)
  line L53 (50.7315, 12) -> (51.3924, 12)
  line L54 (51.3924, 12) -> (52.2113, 14.25)
  line L55 (52.2113, 14.25) -> (53.0542, 14.25)
  line L56 (53.0542, 14.25) -> (53.8731, 12)
  line L57 (53.8731, 12) -> (54.534, 12)
  line L58 (54.534, 12) -> (55.3529, 14.25)
  line L59 (55.3529, 14.25) -> (56.1957, 14.25)
  line L60 (56.1957, 14.25) -> (57.0147, 12)
  line L61 (57.0147, 12) -> (57.6756, 12)
  line L62 (57.6756, 12) -> (58.4945, 14.25)
  line L63 (58.4945, 14.25) -> (59.3373, 14.25)
  line L64 (59.3373, 14.25) -> (60.1563, 12)
  line L65 (60.1563, 12) -> (60.8171, 12)
  line L66 (60.8171, 12) -> (61.6361, 14.25)
  line L67 (61.6361, 14.25) -> (62.4789, 14.25)
  line L68 (62.4789, 14.25) -> (63.2979, 12)
  line L69 (63.2979, 12) -> (63.9587, 12)
  line L70 (63.9587, 12) -> (64.7777, 14.25)
  line L71 (64.7777, 14.25) -> (65.6205, 14.25)
  line L72 (65.6205, 14.25) -> (66.4395, 12)
  line L73 (66.4395, 12) -> (67.1003, 12)
  line L74 (67.1003, 12) -> (67.9193, 14.25)
  line L75 (67.9193, 14.25) -> (68.7621, 14.25)
  line L76 (68.7621, 14.25) -> (69.5811, 12)
  line L77 (69.5811, 12) -> (70.2419, 12)
  line L78 (70.2419, 12) -> (71.0609, 14.25)
  line L79 (71.0609, 14.25) -> (71.9037, 14.25)
  line L80 (71.9037, 14.25) -> (72.7226, 12)
  line L81 (72.7226, 12) -> (73.3835, 12)
  line L82 (73.3835, 12) -> (74.2024, 14.25)
  line L83 (74.2024, 14.25) -> (75.0453, 14.25)
  line L84 (75.0453, 14.25) -> (75.8642, 12)
  line L85 (75.8642, 12) -> (76.5251, 12)
  line L86 (76.5251, 12) -> (77.344, 14.25)
  line L87 (77.344, 14.25) -> (78.1869, 14.25)
  line L88 (78.1869, 14.25) -> (79.0058, 12)
  line L89 (79.0058, 12) -> (79.6667, 12)
  line L90 (79.6667, 12) -> (80.4856, 14.25)
  line L91 (80.4856, 14.25) -> (81.3285, 14.25)
  line L92 (81.3285, 14.25) -> (82.1474, 12)
  line L93 (82.1474, 12) -> (82.8083, 12)
  line L94 (82.8083, 12) -> (83.6272, 14.25)
  line L95 (83.6272, 14.25) -> (84.4701, 14.25)
  line L96 (84.4701, 14.25) -> (85.289, 12)
  line L97 (85.289, 12) -> (85.9499, 12)
  line L98 (85.9499, 12) -> (86.7688, 14.25)
  line L99 (86.7688, 14.25) -> (87.6117, 14.25)
  line L100 (87.6117, 14.25) -> (88.4306, 12)
  line L101 (88.4306, 12) -> (89.0915, 12)
  line L102 (89.0915, 12) -> (89.9104, 14.25)
  line L103 (89.9104, 14.25) -> (90.7533, 14.25)
  line L104 (90.7533, 14.25) -> (91.5722, 12)
  line L105 (91.5722, 12) -> (92.2331, 12)
  line L106 (92.2331, 12) -> (93.052, 14.25)
  line L107 (93.052, 14.25) -> (93.8949, 14.25)
  line L108 (93.8949, 14.25) -> (94.7138, 12)
  line L109 (94.7138, 12) -> (95.3747, 12)
  line L110 (95.3747, 12) -> (96.1936, 14.25)
  line L111 (96.1936, 14.25) -> (97.0365, 14.25)
  line L112 (97.0365, 14.25) -> (97.8554, 12)
  line L113 (97.8554, 12) -> (98.5163, 12)
  line L114 (98.5163, 12) -> (99.3352, 14.25)
  line L115 (99.3352, 14.25) -> (100.178, 14.25)
  line L116 (100.178, 14.25) -> (100.997, 12)
  line L117 (100.997, 12) -> (101.6578, 12)
  line L118 (101.6578, 12) -> (102.4768, 14.25)
  line L119 (102.4768, 14.25) -> (103.3196, 14.25)
  line L120 (103.3196, 14.25) -> (104.1386, 12)
  line L121 (104.1386, 12) -> (104.7994, 12)
  line L122 (104.7994, 12) -> (105.6184, 14.25)
  line L123 (105.6184, 14.25) -> (106.4612, 14.25)
  line L124 (106.4612, 14.25) -> (107.2802, 12)
  line L125 (107.2802, 12) -> (107.941, 12)
  line L126 (107.941, 12) -> (108.76, 14.25)
  line L127 (108.76, 14.25) -> (109.6028, 14.25)
  line L128 (109.6028, 14.25) -> (110.4218, 12)
  line L129 (110.4218, 12) -> (111.0826, 12)
  line L130 (111.0826, 12) -> (111.9016, 14.25)
  line L131 (111.9016, 14.25) -> (112.7444, 14.25)
  line L132 (112.7444, 14.25) -> (113.5633, 12)
  line L133 (113.5633, 12) -> (114.2242, 12)
  line L134 (114.2242, 12) -> (115.0432, 14.25)
  line L135 (115.0432, 14.25) -> (115.886, 14.25)
  line L136 (115.886, 14.25) -> (116.7049, 12)
  line L137 (116.7049, 12) -> (118, 12)
  line L138 (118, 12) -> (118, 11.5)
  line L139 (118, 11.5) -> (8.3, 11.5)
extrude "rack (2)'" add sketch "rack (1) (2)" along normal blind 3.49 separate body makes body 36 in component "Gripper handle (printed)"
ref_plane "WorkPlane7" through (0, 0, -37) normal (0, 0, 1) x (1, 0, 0) in component "Gripper handle (printed)"
sketch "lock bridge" plane through (0, 0, -37) normal (0, 0, 1) x (1, 0, 0) in component "Gripper handle (printed)"
  line L0 (102, 6) -> (114, 6)
  line L1 (114, 6) -> (114, 12)
  line L2 (114, 12) -> (102, 12)
  line L3 (102, 12) -> (102, 6)
extrude "lock bridge (1)" add sketch "lock bridge" along normal blind 25.01 separate body makes body 37 in component "Gripper handle (printed)"
sketch "lock block" plane through (0, 0, -37) normal (0, 0, 1) x (1, 0, 0) in component "Gripper handle (printed)"
  line L0 (102, 6) -> (114, 6)
  line L1 (114, 6) -> (114, 38.8)
  line L2 (114, 38.8) -> (102, 38.8)
  line L3 (102, 38.8) -> (102, 6)
extrude "lock block (1)" add sketch "lock block" along normal blind 8 separate body makes body 38 in component "Gripper handle (printed)"
sketch "cable stop bar" plane through (0, 0, 23.99) normal (0, 0, 1) x (1, 0, 0) in component "Gripper handle (printed)"
  line L0 (98.5, 6) -> (104.5, 6)
  line L1 (104.5, 6) -> (104.5, 16.01)
  line L2 (104.5, 16.01) -> (98.5, 16.01)
  line L3 (98.5, 16.01) -> (98.5, 6)
extrude "cable stop bar (1)" add sketch "cable stop bar" along normal blind 33.022 separate body makes body 39 in component "Gripper handle (printed)"
ref_plane "WorkPlane8" through (0, 0, 47.012) normal (0, 0, 1) x (1, 0, 0) in component "Gripper handle (printed)"
sketch "cable stop" plane through (0, 0, 47.012) normal (0, 0, 1) x (1, 0, 0) in component "Gripper handle (printed)"
  line L0 (98.5, 16) -> (104.5, 16)
  line L1 (104.5, 16) -> (104.5, 31.6)
  line L2 (104.5, 31.6) -> (98.5, 31.6)
  line L3 (98.5, 31.6) -> (98.5, 16)
extrude "cable stop (1)" add sketch "cable stop" along normal blind 10 separate body makes body 40 in component "Gripper handle (printed)"
combine "Combine1''''''" operation add target body 30 tool bodies 31 in component "Gripper handle (printed)"
combine "Combine2''''" operation add target body 30 tool bodies 32 in component "Gripper handle (printed)"
combine "Combine3''" operation add target body 30 tool bodies 37 in component "Gripper handle (printed)"
combine "Combine4''" operation add target body 30 tool bodies 38 in component "Gripper handle (printed)"
combine "Combine5''" operation add target body 30 tool bodies 39 in component "Gripper handle (printed)"
combine "Combine6'" operation add target body 30 tool bodies 40 in component "Gripper handle (printed)"
combine "Combine7'" operation add target body 30 tool bodies 35 in component "Gripper handle (printed)"
combine "Combine8" operation add target body 30 tool bodies 36 in component "Gripper handle (printed)"
combine "Combine9" operation add target body 30 tool bodies 33 in component "Gripper handle (printed)"
combine "Combine10" operation add target body 30 tool bodies 34 in component "Gripper handle (printed)"
ref_plane "WorkPlane9" through (97.5, 0, 0) normal (1, 0, 0) x (0, 1, 0) in component "Gripper handle (printed)"
sketch "wire hole" plane through (97.5, 0, 0) normal (1, 0, 0) x (0, 0, -1) in component "Gripper handle (printed)"
  circle A0 centre (-52.012, 26.6) radius 1
extrude "wire hole (1)" cut sketch "wire hole" along normal blind 8 bodies 30 in component "Gripper handle (printed)"
ref_plane "WorkPlane10" through (0, 22, 0) normal (0, 1, 0) x (0, 0, 1) in component "Gripper handle (printed)"
sketch "nipple relief" plane through (0, 22, 0) normal (0, 1, 0) x (1, 0, 0) in component "Gripper handle (printed)"
  line L0 (140.1203, -58.012) -> (140.0521, -58.5297)
  line L1 (140.0521, -58.5297) -> (139.8523, -59.012)
  line L2 (139.8523, -59.012) -> (139.5345, -59.4262)
  line L3 (139.5345, -59.4262) -> (139.1203, -59.7441)
  line L4 (139.1203, -59.7441) -> (138.6379, -59.9439)
  line L5 (138.6379, -59.9439) -> (138.1203, -60.012)
  line L6 (138.1203, -60.012) -> (122.1203, -60.012)
  line L7 (122.1203, -60.012) -> (121.6026, -59.9439)
  line L8 (121.6026, -59.9439) -> (121.1203, -59.7441)
  line L9 (121.1203, -59.7441) -> (120.7061, -59.4262)
  line L10 (120.7061, -59.4262) -> (120.3882, -59.012)
  line L11 (120.3882, -59.012) -> (120.1884, -58.5297)
  line L12 (120.1884, -58.5297) -> (120.1203, -58.012)
  line L13 (120.1203, -58.012) -> (120.1203, -46.012)
  line L14 (120.1203, -46.012) -> (120.1884, -45.4944)
  line L15 (120.1884, -45.4944) -> (120.3882, -45.012)
  line L16 (120.3882, -45.012) -> (120.7061, -44.5978)
  line L17 (120.7061, -44.5978) -> (121.1203, -44.28)
  line L18 (121.1203, -44.28) -> (121.6026, -44.0802)
  line L19 (121.6026, -44.0802) -> (122.1203, -44.012)
  line L20 (122.1203, -44.012) -> (138.1203, -44.012)
  line L21 (138.1203, -44.012) -> (138.6379, -44.0802)
  line L22 (138.6379, -44.0802) -> (139.1203, -44.28)
  line L23 (139.1203, -44.28) -> (139.5345, -44.5978)
  line L24 (139.5345, -44.5978) -> (139.8523, -45.012)
  line L25 (139.8523, -45.012) -> (140.0521, -45.4944)
  line L26 (140.0521, -45.4944) -> (140.1203, -46.012)
  line L27 (140.1203, -46.012) -> (140.1203, -58.012)
extrude "nipple relief (1)" cut sketch "nipple relief" along normal blind 3 bodies 30 in component "Gripper handle (printed)"
ref_plane "WorkPlane11" through (0, 0, -38) normal (0, 0, 1) x (1, 0, 0) in component "Gripper handle (printed)"
sketch "plunger hole" plane through (0, 0, -38) normal (0, 0, 1) x (1, 0, 0) in component "Gripper handle (printed)"
  circle A0 centre (108, 36) radius 4
extrude "plunger hole (1)" cut sketch "plunger hole" along normal blind 10 bodies 30 in component "Gripper handle (printed)"
ref_plane "WorkPlane12" through (0, 0, -10) normal (0, 0, 1) x (1, 0, 0) in component "Gripper handle (printed)"
sketch "pivot hole (2)" plane through (0, 0, -10) normal (0, 0, 1) x (1, 0, 0) in component "Gripper handle (printed)"
  circle A0 centre (100, -4) radius 1.7
extrude "pivot hole (1)'" cut sketch "pivot hole (2)" along normal blind 36 bodies 30 in component "Gripper handle (printed)"
ref_plane "WorkPlane13" through (0, 0, 11.5) normal (0, 0, 1) x (1, 0, 0) in component "Gripper handle (printed)"
sketch "horn slot" plane through (0, 0, 11.5) normal (0, 0, 1) x (1, 0, 0) in component "Gripper handle (printed)"
  line L0 (93.5, 5) -> (118, 5)
  line L1 (118, 5) -> (118, 18.5)
  line L2 (118, 18.5) -> (93.5, 18.5)
  line L3 (93.5, 18.5) -> (93.5, 5)
extrude "horn slot (1)" cut sketch "horn slot" along normal blind 9 bodies 30 in component "Gripper handle (printed)"
ref_plane "WorkPlane14" through (0, 0, 13.3) normal (0, 0, 1) x (1, 0, 0) in component "Gripper handle (printed)"
sketch "housing pocket" plane through (0, 0, 13.3) normal (0, 0, 1) x (1, 0, 0) in component "Gripper handle (printed)"
  line L0 (55, 10.8) -> (89, 10.8)
  line L1 (89, 10.8) -> (89, 16.2)
  line L2 (89, 16.2) -> (55, 16.2)
  line L3 (55, 16.2) -> (55, 10.8)
extrude "housing pocket (1)" cut sketch "housing pocket" along normal blind 11.7 bodies 30 in component "Gripper handle (printed)"
ref_plane "WorkPlane15" through (88, 0, 0) normal (1, 0, 0) x (0, 1, 0) in component "Gripper handle (printed)"
sketch "wire hole (1)" plane through (88, 0, 0) normal (1, 0, 0) x (0, 0, -1) in component "Gripper handle (printed)"
  circle A0 centre (-16, 13.5) radius 1
extrude "wire hole (2)" cut sketch "wire hole (1)" along normal blind 6.5 bodies 30 in component "Gripper handle (printed)"
ref_plane "WorkPlane16" through (7.3, 0, 0) normal (1, 0, 0) x (0, 1, 0) in component "Gripper handle (printed)"
sketch "flange screw hole" plane through (7.3, 0, 0) normal (1, 0, 0) x (0, 0, -1) in component "Gripper handle (printed)"
  circle A0 centre (-5, 9.5) radius 1.7